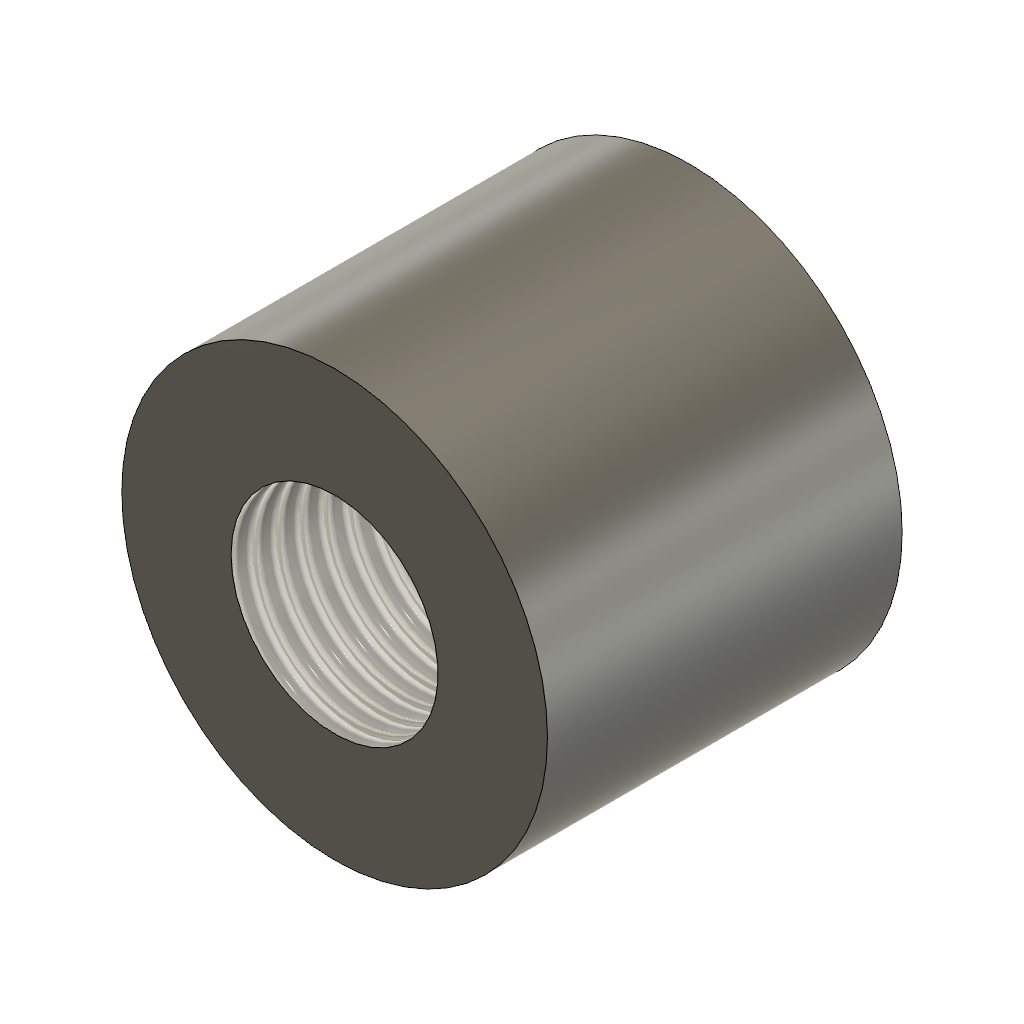
bsp_pipe_internal (Autodesk Fusion 360 design; units mm, degrees)
part number: 2026-10-21-16-02-15-999
Autodesk Fusion 360 part; units mm, degrees
sketch "OwnedThreadProfile_0_bsp_pipe_internal" plane through (0, 0, 0) normal (0, 0, 1) x (1, 0, 0)
  circle A0 centre (0, 0) radius 6
  circle A1 centre (0, 0) radius 12
extrude "OwnedThreadCylinderExtrude_0_bsp_pipe_internal" add sketch "OwnedThreadProfile_0_bsp_pipe_internal" along normal blind 20
thread "OwnedThreadFamily_bsp_pipe_internal" "BSP Pipe Threads 1/4 G 1/4-19 G 1/4-19" major diameter 13.157 minor diameter 11.6675 pitch 1.3368 angle 55 resizes the face on face at (5.9925, -0.2991, 13.3333)
named bodies: "OwnedThreadCylinder_0_bsp_pipe_internal"
